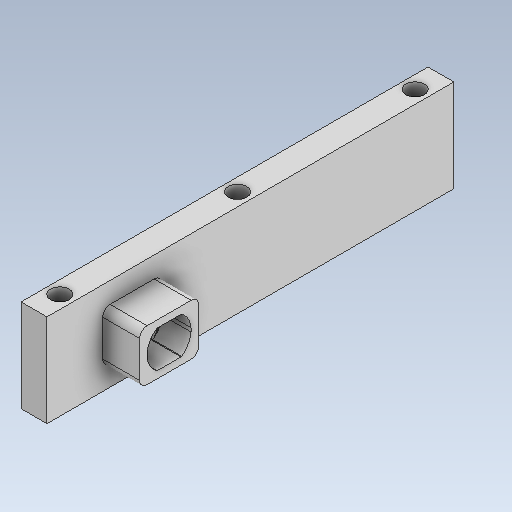
# Autodesk Inventor part: Seitenteil_innen
Saved by Autodesk Inventor 2026.4 (Build 304435000, 435)
## iProperties
Created: 2026-11-13
Part Number: Seitenteil_innen
Material: Generisch
Document SubType Name: Modeling
Designer: weira
Density: 1 g/cm^3
Appearance: Vorgabe
Mass: 28.5302 g
Surface Area: 114.341 cm^2
Volume: 28.5302 cm^3
Author: weira
Autodesk Inventor part; units mm, degrees
ref_plane "YZ Plane" through (0, 0, 0) normal (1, 0, 0) x (0, 1, 0)
ref_plane "XZ Plane" through (0, 0, 0) normal (0, 1, 0) x (-1, 0, 0)
ref_plane "XY Plane" through (0, 0, 0) normal (0, 0, 1) x (1, 0, 0)
sketch "Skizze1" plane through (0, 0, 0) normal (1, 0, 0) x (0, 1, 0)
  line L0 (55, 12.5) -> (-55, 12.5)
  line L1 (-55, 12.5) -> (-55, -12.5)
  line L2 (-55, -12.5) -> (55, -12.5)
  line L3 (55, -12.5) -> (55, 12.5)
  line L4 (55, 12.5) -> (-55, -12.5) construction
  line L5 (-55, 12.5) -> (55, -12.5) construction
  circle A0 centre (-32, 0) radius 8.5
  circle A1 centre (30, 0) radius 8.5
  line L6 (-26.05, 4.9) -> (-37.95, 4.9)
  line L7 (-37.95, 4.9) -> (-37.95, -4.9)
  line L8 (-37.95, -4.9) -> (-26.05, -4.9)
  line L9 (-26.05, -4.9) -> (-26.05, 4.9)
  line L10 (-26.05, 4.9) -> (-37.95, -4.9) construction
  line L11 (-37.95, 4.9) -> (-26.05, -4.9) construction
  point P0 (0, 0)
  dimension "d0" = 110
  dimension "d1" = 25
  dimension "d7" = 17
  dimension "d8" = 17
  dimension "d9" = 62
  dimension "d10" = 23
  dimension "d16" = 9.8
  dimension "d17" = 11.9
  constraints: 24 end point, 4 midpoint, 4 parallel, 2 centre point, 2 horizontal, 2 perpendicular
  measures "d0" distance of L0.start L0.end
  measures "d1" distance of L0.end L1.end
  measures "d7" diameter of A1
  measures "d8" diameter of A0
  measures "d9" distance of A0.centre A1.centre
  measures "d10" distance from line of L1 A0.centre
  measures "d16" distance of L6.end L7.end
  measures "d17" distance of L6.start L6.end
extrude "Extrusion1" add sketch "Skizze1" along normal blind 7 contours L3 L2 L1 L0 | A0 | A1
sketch "Skizze8" plane through (7, 0, 0) normal (1, 0, 0) x (0, 0, -1)
  line L0 (-12.5, -55) -> (12.5, -55) projected
  line L1 (12.5, -55) -> (12.5, 55) projected
  line L2 (12.5, 55) -> (-12.5, 55) projected
  line L3 (-12.5, 55) -> (-12.5, -55) projected
  line L4 (-4.9, -26.05) -> (4.9, -26.05) projected
  line L5 (4.9, -26.05) -> (4.9, -37.95) projected
  line L6 (4.9, -37.95) -> (-4.9, -37.95) projected
  line L7 (-4.9, -37.95) -> (-4.9, -26.05) projected
  line L8 (-6.9, -39.95) -> (6.9, -39.95)
  line L9 (6.9, -39.95) -> (6.9, -24.05)
  line L10 (6.9, -24.05) -> (-6.9, -24.05)
  line L11 (-6.9, -24.05) -> (-6.9, -39.95)
  point P0 (0, 0)
  dimension "d47" = 2
  dimension "d48" = 2
  dimension "d49" = 2
  dimension "d50" = 2
  constraints: 8 end point, 2 parallel, 1 horizontal, 1 perpendicular
  measures "d47" distance between parallel lines of L11 L7
  measures "d48" distance between parallel lines of L8 L6
  measures "d49" distance between parallel lines of L10 L4
  measures "d50" distance between parallel lines of L5 L9
extrude "Extrusion9" add sketch "Skizze8" along normal blind 2 contours L11 L10 L9 L8
sketch "Skizze9" plane through (9, 0, 0) normal (1, 0, 0) x (0, 0, -1)
  line L0 (6.9, -39.95) -> (6.9, -24.05)
  line L1 (6.9, -24.05) -> (-6.9, -24.05)
  line L2 (-6.9, -24.05) -> (-6.9, -39.95)
  line L3 (-6.9, -39.95) -> (6.9, -39.95)
  line L4 (-4.9, -26.05) -> (4.9, -26.05)
  line L5 (4.9, -26.05) -> (4.9, -37.95)
  line L6 (4.9, -37.95) -> (-4.9, -37.95)
  line L7 (-4.9, -37.95) -> (-4.9, -26.05)
  line L8 (-4.9, -37.95) -> (4.9, -26.05) construction
  line L9 (-4.9, -26.05) -> (4.9, -37.95) construction
  line L10 (6.75, -102.9247) -> (6.75, -96.4742)
  spline S0 degree 3 poles (6.75, -96.4742) (5.7653, -94.9476) (4.0559, -93.9228) (2.25, -93.7705) knots 0 0 0 0 1 1 1 1
  spline S1 degree 3 poles (1.25, -93.7705) (-0.556, -93.9228) (-2.2653, -94.9476) (-3.25, -96.4742) knots 0 0 0 0 1 1 1 1
  spline S2 degree 3 poles (2.25, -93.7705) (2.0837, -93.7565) (1.9169, -93.7494) (1.5831, -93.7494) (1.4163, -93.7565) (1.25, -93.7705) knots 0 0 0 0 0.5 0.5 1 1 1 1
  line L11 (-3.25, -96.4742) -> (-3.25, -102.9247)
  spline S3 degree 3 poles (-3.25, -102.9247) (-2.2653, -104.4513) (-0.556, -105.4761) (1.25, -105.6284) knots 0 0 0 0 1 1 1 1
  spline S4 degree 3 poles (2.25, -105.6284) (4.0559, -105.4761) (5.7653, -104.4513) (6.75, -102.9247) knots 0 0 0 0 1 1 1 1
  line L12 (6.65, -103.0747) -> (6.65, -105.1494)
  line L13 (6.65, -94.2494) -> (6.65, -96.3242)
  arc A0 (6.65, -94.2494) -> (6.15, -93.7494) centre (6.15, -94.2494) ccw
  line L14 (1.75, -93.7494) -> (6.15, -93.7494)
  line L15 (-2.65, -93.7494) -> (1.75, -93.7494)
  line L16 (-3.15, -96.3242) -> (-3.15, -94.2494)
  arc A1 (-2.65, -93.7494) -> (-3.15, -94.2494) centre (-2.65, -94.2494) ccw
  line L17 (-3.15, -105.1494) -> (-3.15, -103.0747)
  arc A2 (-3.15, -105.1494) -> (-2.65, -105.6494) centre (-2.65, -105.1494) ccw
  line L18 (1.75, -105.6494) -> (-2.65, -105.6494)
  line L19 (6.15, -105.6494) -> (1.75, -105.6494)
  spline S5 degree 3 poles (1.25, -105.6284) (1.4163, -105.6424) (1.5831, -105.6494) (1.9169, -105.6494) (2.0837, -105.6424) (2.25, -105.6284) knots 0 0 0 0 0.5 0.5 1 1 1 1
  arc A3 (6.15, -105.6494) -> (6.65, -105.1494) centre (6.15, -105.1494) ccw
  line L20 (5, -35.2253) -> (5, -28.7747)
  spline S6 degree 3 poles (5, -28.7747) (4.0153, -27.2482) (2.306, -26.2233) (0.5, -26.071) knots 0 0 0 0 1 1 1 1
  spline S7 degree 3 poles (-0.5, -26.071) (-2.306, -26.2233) (-4.0153, -27.2482) (-5, -28.7747) knots 0 0 0 0 1 1 1 1
  spline S8 degree 3 poles (0.5, -26.071) (0.3337, -26.057) (0.1669, -26.05) (-0.1669, -26.05) (-0.3337, -26.057) (-0.5, -26.071) knots 0 0 0 0 0.5 0.5 1 1 1 1
  line L21 (-5, -28.7747) -> (-5, -35.2253)
  spline S9 degree 3 poles (-5, -35.2253) (-4.0153, -36.7518) (-2.306, -37.7767) (-0.5, -37.929) knots 0 0 0 0 1 1 1 1
  spline S10 degree 3 poles (0.5, -37.929) (2.306, -37.7767) (4.0153, -36.7518) (5, -35.2253) knots 0 0 0 0 1 1 1 1
  line L22 (4.9, -35.3753) -> (4.9, -37.45)
  line L23 (4.9, -26.55) -> (4.9, -28.6247)
  arc A4 (4.9, -26.55) -> (4.4, -26.05) centre (4.4, -26.55) ccw
  line L24 (0, -26.05) -> (4.4, -26.05)
  line L25 (-4.4, -26.05) -> (0, -26.05)
  line L26 (-4.9, -28.6247) -> (-4.9, -26.55)
  arc A5 (-4.4, -26.05) -> (-4.9, -26.55) centre (-4.4, -26.55) ccw
  line L27 (-4.9, -37.45) -> (-4.9, -35.3753)
  arc A6 (-4.9, -37.45) -> (-4.4, -37.95) centre (-4.4, -37.45) ccw
  line L28 (0, -37.95) -> (-4.4, -37.95)
  line L29 (4.4, -37.95) -> (0, -37.95)
  spline S11 degree 3 poles (-0.5, -37.929) (-0.3337, -37.943) (-0.1669, -37.95) (0.1669, -37.95) (0.3337, -37.943) (0.5, -37.929) knots 0 0 0 0 0.5 0.5 1 1 1 1
  arc A7 (4.4, -37.95) -> (4.9, -37.45) centre (4.4, -37.45) ccw
  line L30 (-4.9, -28.1383) -> (-1.8269, -26.05)
  line L31 (0, -32) -> (-2.3883, -32) construction
  line L32 (0, -32) -> (0, -35.2253) construction
  line L33 (-4.9, -35.8617) -> (-1.8269, -37.95)
  line L34 (4.9, -28.1383) -> (1.8269, -26.05)
  line L35 (4.9, -35.8617) -> (1.8269, -37.95)
  point P0 (0, 0)
  point P1 (0, -32)
  point P2 (1.75, -99.6994)
  point P3 (4.9, -28.625)
  point P4 (4.9, -35.375)
  point P5 (-4.9, -35.375)
  point P6 (-4.9, -28.625)
  constraints: 56 end point, 16 point on circle, 8 centre point, 6 symmetric about line, 2 point on line, 1 horizontal, 1 midpoint, 1 vertical, 36 other
extrude "Extrusion10" cut sketch "Skizze9" against normal through all contours L7 S9 L21 S7 | S6 L20 S10 L5
extrude "Extrusion11" add sketch "Skizze9" along normal blind 0.2 contours L3 L2 L1 L0 | L4 A5 L7 | L4 L30 L7 A5 | L4 A4 L5 L34 | L4 L5 A4 | L33 L6 A6 L7 | A6 L6 L7 | L5 A7 L6 L35 | L5 L6 A7
sketch "Skizze10" plane through (9.2, 0, 0) normal (1, 0, 0) x (0, 0, -1)
  line L0 (6.9, -39.95) -> (-6.9, -39.95)
  line L1 (-6.9, -39.95) -> (-6.9, -24.05)
  line L2 (-6.9, -24.05) -> (6.9, -24.05)
  line L3 (6.9, -24.05) -> (6.9, -39.95)
  line L4 (-12.5, -55) -> (12.5, -55)
  line L5 (12.5, -55) -> (12.5, 55)
  line L6 (12.5, 55) -> (-12.5, 55)
  line L7 (-12.5, 55) -> (-12.5, -55)
  spline S0 degree 3 poles (-5, -35.2253) (-4.0153, -36.7518) (-2.306, -37.7767) (-0.5, -37.929) knots 0 0 0 0 1 1 1 1
  spline S1 degree 3 poles (0.5, -37.929) (2.306, -37.7767) (4.0153, -36.7518) (5, -35.2253) knots 0 0 0 0 1 1 1 1
  line L8 (6.9, -24.05) -> (-6.9, -24.05)
  line L9 (-6.9, -24.05) -> (-6.9, -39.95)
  line L10 (-6.9, -39.95) -> (6.9, -39.95)
  line L11 (6.9, -39.95) -> (6.9, -24.05)
  line L12 (4.9, -28.1383) -> (4.9, -28.625)
  arc A0 (5, -28.7747) -> (4.9, -28.625) centre (0.2565, -31.8347) ccw
  line L13 (5, -28.7747) -> (5, -35.2253)
  arc A1 (4.9, -35.375) -> (5, -35.2253) centre (0.2565, -32.1653) ccw
  line L14 (4.9, -35.375) -> (4.9, -35.8617)
  line L15 (4.9, -35.8617) -> (1.8269, -37.95)
  line L16 (1.8269, -37.95) -> (-1.8269, -37.95)
  line L17 (-1.8269, -37.95) -> (-4.9, -35.8617)
  line L18 (-4.9, -35.8617) -> (-4.9, -35.375)
  arc A2 (-5, -35.2253) -> (-4.9, -35.375) centre (-0.2565, -32.1653) ccw
  line L19 (-5, -35.2253) -> (-5, -28.7747)
  arc A3 (-4.9, -28.625) -> (-5, -28.7747) centre (-0.2565, -31.8347) ccw
  line L20 (-4.9, -28.625) -> (-4.9, -28.1383)
  line L21 (-4.9, -28.1383) -> (-1.8269, -26.05)
  line L22 (-1.8269, -26.05) -> (1.8269, -26.05)
  line L23 (1.8269, -26.05) -> (4.9, -28.1383)
  spline S2 degree 3 poles (-0.5, -26.071) (-2.306, -26.2233) (-4.0153, -27.2482) (-5, -28.7747) knots 0 0 0 0 1 1 1 1
  spline S3 degree 3 poles (5, -28.7747) (4.0153, -27.2482) (2.306, -26.2233) (0.5, -26.071) knots 0 0 0 0 1 1 1 1
  spline S4 degree 3 poles (0.5, -26.071) (0.3337, -26.057) (0.1669, -26.05) (-0.1669, -26.05) (-0.3337, -26.057) (-0.5, -26.071) knots 0 0 0 0 0.5 0.5 1 1 1 1
  spline S5 degree 3 poles (-0.5, -37.929) (-0.3337, -37.943) (-0.1669, -37.95) (0.1669, -37.95) (0.3337, -37.943) (0.5, -37.929) knots 0 0 0 0 0.5 0.5 1 1 1 1
  point P0 (0, 0)
  point P1 (0, -32)
  point P2 (5, -35.2253)
extrude "Extrusion12" add sketch "Skizze10" along normal blind 7.8 contours L0 L1 L2 L3 | S0 S5 L16 L17 L18 | L20 L21 L22 S4 S2 | S5 S1 L14 L15 L16 | L22 L23 L12 S3 S4
fillet "Rundung2" radius 2 4 edges at (12, -39.95, -6.9) (12, -39.95, 6.9) (12, -24.05, -6.9) (12, -24.05, 6.9)
extrude "Extrusion13" cut sketch "Skizze1" along normal blind 5 contours A1
sketch "Skizze11" plane through (0, -55, 12.5) normal (0, 0, 1) x (1, 0, 0)
  line L0 (0, 110) -> (0, 0) projected
  line L1 (0, 0) -> (7, 0) projected
  line L2 (7, 110) -> (7, 0) projected
  line L3 (0, 110) -> (7, 110) projected
  point P0 (0, 55)
  point P1 (3.5, 103)
  point P2 (3.5, 7)
  point P3 (3.5, 55)
  dimension "d62" = 7
  dimension "d63" = 7
  dimension "d64" = 7
  dimension "d65" = 3.5
  dimension "d66" = 3.5
  dimension "d67" = 3.5
  dimension "d68" = 96
  dimension "d69" = 48
  measures "d62" distance from line of L3 point (3.5, 103)
  measures "d63" distance between parallel lines of L0 L2
  measures "d64" distance from line of L1 point (3.5, 7)
  measures "d65" distance from line of L0 point (3.5, 7)
  measures "d66" distance from line of L0 point (3.5, 103)
  measures "d67" distance from line of L0 point (3.5, 55)
  measures "d68" distance of point (3.5, 7) point (3.5, 103)
  measures "d69" distance of point (3.5, 103) point (3.5, 55)
hole "Bohrung1" at (3.5, 48, 12.5) at (3.5, -48, 12.5) at (3.5, 0, 12.5) direction (0, 0, -1) diameter 5 end through all
equation "\"d7\" = d8"
equation "\"d48\" = d47"
equation "\"d49\" = d47"
equation "\"d50\" = d49"
equation "\"d69\" = 0.5 * d68"
